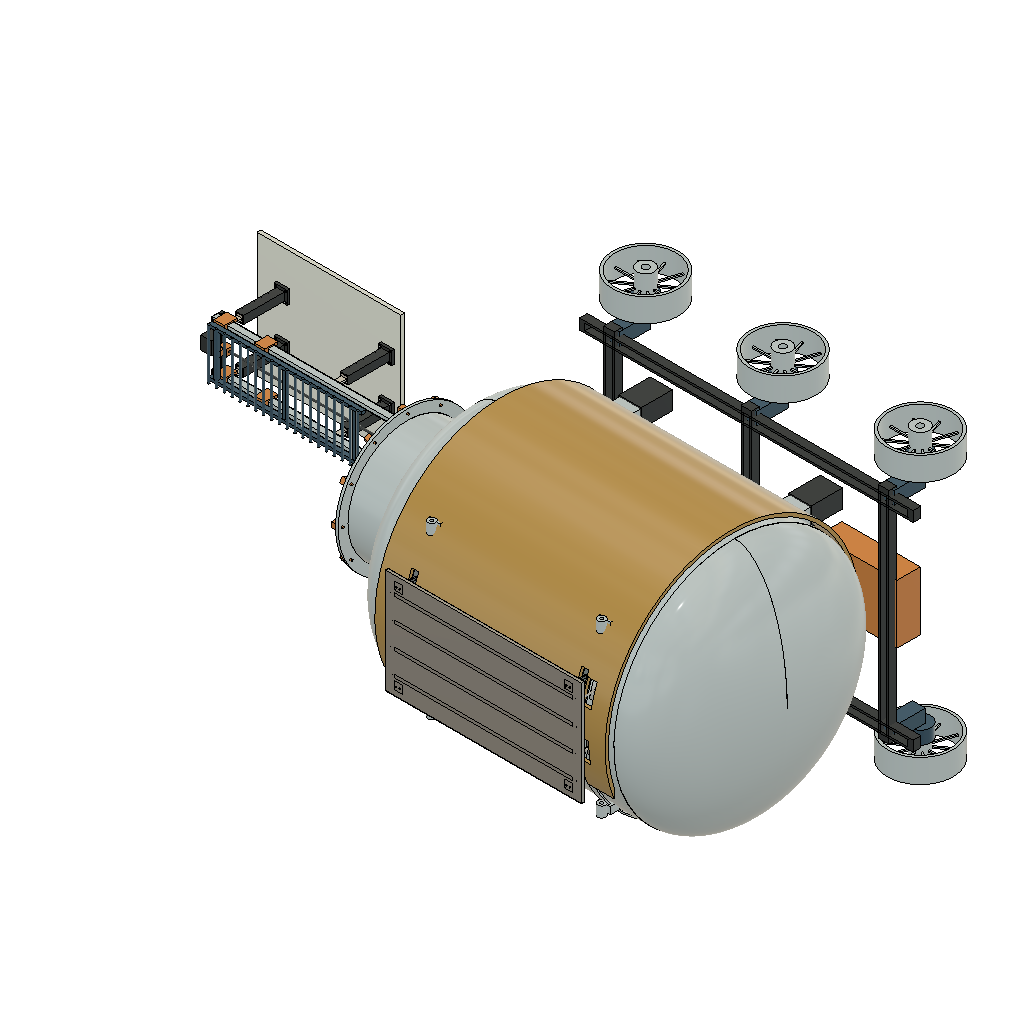
Moon_Movers_Concept (Autodesk Fusion 360 design; units mm, degrees)
part number: 2026-11-06-12-02-36-171
part number: 2026-11-06-12-02-36-298
part number: 2026-11-06-12-02-36-385
part number: 2026-11-06-12-02-36-736
part number: 2026-11-06-12-02-36-965
part number: 2026-11-06-12-02-37-148
part number: 2026-11-06-12-02-37-479
part number: 2026-11-06-12-02-37-621
part number: 2026-11-06-12-02-38-111
part number: 2026-11-06-12-02-38-668
part number: 2026-11-06-12-02-39-496
part number: 2026-11-06-12-02-40-582
part number: 2026-11-06-12-02-49-881
part number: 2026-11-06-12-02-51-442
part number: 2026-11-06-12-02-57-984
part number: 2026-11-06-12-02-58-352
part number: 2026-11-06-12-02-58-724
part number: 2026-11-06-12-02-59-677
part number: 2026-11-06-12-03-03-680
part number: 2026-11-06-12-03-06-963
part number: 2026-11-06-12-03-10-567
part number: 2026-11-06-12-03-15-193
part number: 2026-11-06-12-03-15-696
part number: 2026-11-06-12-26-54-918
part number: 2026-11-06-12-26-55-866
part number: 2026-11-06-12-26-57-242
part number: 2026-11-06-12-27-05-281
part number: 2026-11-06-13-09-31-180
part number: 2026-11-06-13-09-33-075
part number: 2026-11-06-13-09-46-178
part number: 2026-11-06-13-09-54-767
part number: 2026-11-06-13-09-58-459
part number: 2026-11-06-13-17-13-967
part number: 2026-11-06-13-17-21-409
part number: 2026-11-06-17-33-04-361
part number: 2026-11-06-17-33-16-586
part number: 2026-11-06-17-33-29-540
part number: 2026-11-06-17-34-03-018
Autodesk Fusion 360 part; units mm, degrees
(part 1 of 5)
sketch "Closed pressure shell meridian 3 mm" plane through (0, 0, 0) normal (0, 0, 1) x (1, 0, 0) in component "MM01 Pressure shell and neck"
  ellipse E0 centre (-900, 0) end of major axis (-900, 923) minor radius 403 (-900, 923) -> (-1303, 0) ccw
  ellipse E1 centre (-900, 0) end of major axis (-900, 920) minor radius 400 (-900, 920) -> (-1300, 0) ccw
  ellipse E2 centre (900, 0) end of major axis (900, 923) minor radius 403 (900, 923) -> (1303, 0) cw
  ellipse E3 centre (900, 0) end of major axis (900, 920) minor radius 400 (900, 920) -> (1300, 0) cw
  line L0 (-900, 923) -> (900, 923)
  line L1 (-900, 920) -> (900, 920)
  line L2 (-1303, 0) -> (-1300, 0)
  line L3 (1303, 0) -> (1300, 0)
revolve "Revolved barrel and ellipsoidal heads" add sketch "Closed pressure shell meridian 3 mm" angle 360 about axis through (1.75, 0, 0) along (1, 0, 0) contours  makes body 1 in component "MM01 Pressure shell and neck"
ref_plane "WorkPlane1" through (-1650, 0, 0) normal (1, 0, 0) x (0, 1, 0) in component "MM01 Pressure shell and neck"
sketch "Front pressure port sketch" plane through (-1650, 0, 0) normal (1, 0, 0) x (0, 0, -1) in component "MM01 Pressure shell and neck"
  circle A0 centre (0, 0) radius 450
extrude "Front pressure port" cut sketch "Front pressure port sketch" along normal blind 700 bodies 1 in component "MM01 Pressure shell and neck"
ref_plane "WorkPlane2" through (-1600, 0, 0) normal (1, 0, 0) x (0, 1, 0) in component "MM01 Pressure shell and neck"
sketch "Pressure transfer neck sketch" plane through (-1600, 0, 0) normal (1, 0, 0) x (0, 0, -1) in component "MM01 Pressure shell and neck"
  circle A0 centre (0, 0) radius 455
  circle A1 centre (0, 0) radius 450
extrude "Pressure transfer neck" add sketch "Pressure transfer neck sketch" along normal blind 400 bodies 1 in component "MM01 Pressure shell and neck"
ref_plane "WorkPlane1" through (-1620, 0, 0) normal (1, 0, 0) x (0, 1, 0) in component "MM02 Berthing flange and clear aperture"
sketch "Berthing face sketch" plane through (-1620, 0, 0) normal (1, 0, 0) x (0, 0, -1) in component "MM02 Berthing flange and clear aperture"
  circle A0 centre (0, 0) radius 530
extrude "Berthing face" add sketch "Berthing face sketch" along normal blind 20 separate body makes body 2 in component "MM02 Berthing flange and clear aperture"
ref_plane "WorkPlane2" through (0, 0, -235) normal (0, 0, 1) x (1, 0, 0) in component "MM02 Berthing flange and clear aperture"
sketch "Clear hatch 670 x 470 sketch" plane through (0, 0, -235) normal (0, 0, 1) x (1, 0, 0) in component "MM02 Berthing flange and clear aperture"
  line L0 (-1650, -335) -> (-1570, -335)
  line L1 (-1570, -335) -> (-1570, 335)
  line L2 (-1570, 335) -> (-1650, 335)
  line L3 (-1650, 335) -> (-1650, -335)
extrude "Clear hatch 670 x 470" cut sketch "Clear hatch 670 x 470 sketch" along normal blind 470 bodies 2 in component "MM02 Berthing flange and clear aperture"
ref_plane "WorkPlane3" through (-1640, 0, 0) normal (1, 0, 0) x (0, 1, 0) in component "MM02 Berthing flange and clear aperture"
sketch "Capture fastener bore 1 sketch" plane through (-1640, 0, 0) normal (1, 0, 0) x (0, 0, -1) in component "MM02 Berthing flange and clear aperture"
  circle A0 centre (0, 500) radius 8
extrude "Capture fastener bore 1" cut sketch "Capture fastener bore 1 sketch" along normal blind 60 bodies 2 in component "MM02 Berthing flange and clear aperture"
ref_plane "WorkPlane4" through (-1640, 0, 0) normal (1, 0, 0) x (0, 1, 0) in component "MM02 Berthing flange and clear aperture"
sketch "Capture fastener bore 2 sketch" plane through (-1640, 0, 0) normal (1, 0, 0) x (0, 0, -1) in component "MM02 Berthing flange and clear aperture"
  circle A0 centre (-250, 433.0127) radius 8
extrude "Capture fastener bore 2" cut sketch "Capture fastener bore 2 sketch" along normal blind 60 bodies 2 in component "MM02 Berthing flange and clear aperture"
ref_plane "WorkPlane5" through (-1640, 0, 0) normal (1, 0, 0) x (0, 1, 0) in component "MM02 Berthing flange and clear aperture"
sketch "Capture fastener bore 3 sketch" plane through (-1640, 0, 0) normal (1, 0, 0) x (0, 0, -1) in component "MM02 Berthing flange and clear aperture"
  circle A0 centre (-433.0127, 250) radius 8
extrude "Capture fastener bore 3" cut sketch "Capture fastener bore 3 sketch" along normal blind 60 bodies 2 in component "MM02 Berthing flange and clear aperture"
ref_plane "WorkPlane6" through (-1640, 0, 0) normal (1, 0, 0) x (0, 1, 0) in component "MM02 Berthing flange and clear aperture"
sketch "Capture fastener bore 4 sketch" plane through (-1640, 0, 0) normal (1, 0, 0) x (0, 0, -1) in component "MM02 Berthing flange and clear aperture"
  circle A0 centre (-500, 0) radius 8
extrude "Capture fastener bore 4" cut sketch "Capture fastener bore 4 sketch" along normal blind 60 bodies 2 in component "MM02 Berthing flange and clear aperture"
ref_plane "WorkPlane7" through (-1640, 0, 0) normal (1, 0, 0) x (0, 1, 0) in component "MM02 Berthing flange and clear aperture"
sketch "Capture fastener bore 5 sketch" plane through (-1640, 0, 0) normal (1, 0, 0) x (0, 0, -1) in component "MM02 Berthing flange and clear aperture"
  circle A0 centre (-433.0127, -250) radius 8
extrude "Capture fastener bore 5" cut sketch "Capture fastener bore 5 sketch" along normal blind 60 bodies 2 in component "MM02 Berthing flange and clear aperture"
ref_plane "WorkPlane8" through (-1640, 0, 0) normal (1, 0, 0) x (0, 1, 0) in component "MM02 Berthing flange and clear aperture"
sketch "Capture fastener bore 6 sketch" plane through (-1640, 0, 0) normal (1, 0, 0) x (0, 0, -1) in component "MM02 Berthing flange and clear aperture"
  circle A0 centre (-250, -433.0127) radius 8
extrude "Capture fastener bore 6" cut sketch "Capture fastener bore 6 sketch" along normal blind 60 bodies 2 in component "MM02 Berthing flange and clear aperture"
ref_plane "WorkPlane9" through (-1640, 0, 0) normal (1, 0, 0) x (0, 1, 0) in component "MM02 Berthing flange and clear aperture"
sketch "Capture fastener bore 7 sketch" plane through (-1640, 0, 0) normal (1, 0, 0) x (0, 0, -1) in component "MM02 Berthing flange and clear aperture"
  circle A0 centre (0, -500) radius 8
extrude "Capture fastener bore 7" cut sketch "Capture fastener bore 7 sketch" along normal blind 60 bodies 2 in component "MM02 Berthing flange and clear aperture"
ref_plane "WorkPlane10" through (-1640, 0, 0) normal (1, 0, 0) x (0, 1, 0) in component "MM02 Berthing flange and clear aperture"
sketch "Capture fastener bore 8 sketch" plane through (-1640, 0, 0) normal (1, 0, 0) x (0, 0, -1) in component "MM02 Berthing flange and clear aperture"
  circle A0 centre (250, -433.0127) radius 8
extrude "Capture fastener bore 8" cut sketch "Capture fastener bore 8 sketch" along normal blind 60 bodies 2 in component "MM02 Berthing flange and clear aperture"
ref_plane "WorkPlane11" through (-1640, 0, 0) normal (1, 0, 0) x (0, 1, 0) in component "MM02 Berthing flange and clear aperture"
sketch "Capture fastener bore 9 sketch" plane through (-1640, 0, 0) normal (1, 0, 0) x (0, 0, -1) in component "MM02 Berthing flange and clear aperture"
  circle A0 centre (433.0127, -250) radius 8
extrude "Capture fastener bore 9" cut sketch "Capture fastener bore 9 sketch" along normal blind 60 bodies 2 in component "MM02 Berthing flange and clear aperture"
ref_plane "WorkPlane12" through (-1640, 0, 0) normal (1, 0, 0) x (0, 1, 0) in component "MM02 Berthing flange and clear aperture"
sketch "Capture fastener bore 10 sketch" plane through (-1640, 0, 0) normal (1, 0, 0) x (0, 0, -1) in component "MM02 Berthing flange and clear aperture"
  circle A0 centre (500, 0) radius 8
extrude "Capture fastener bore 10" cut sketch "Capture fastener bore 10 sketch" along normal blind 60 bodies 2 in component "MM02 Berthing flange and clear aperture"
ref_plane "WorkPlane13" through (-1640, 0, 0) normal (1, 0, 0) x (0, 1, 0) in component "MM02 Berthing flange and clear aperture"
sketch "Capture fastener bore 11 sketch" plane through (-1640, 0, 0) normal (1, 0, 0) x (0, 0, -1) in component "MM02 Berthing flange and clear aperture"
  circle A0 centre (433.0127, 250) radius 8
extrude "Capture fastener bore 11" cut sketch "Capture fastener bore 11 sketch" along normal blind 60 bodies 2 in component "MM02 Berthing flange and clear aperture"
ref_plane "WorkPlane14" through (-1640, 0, 0) normal (1, 0, 0) x (0, 1, 0) in component "MM02 Berthing flange and clear aperture"
sketch "Capture fastener bore 12 sketch" plane through (-1640, 0, 0) normal (1, 0, 0) x (0, 0, -1) in component "MM02 Berthing flange and clear aperture"
  circle A0 centre (250, 433.0127) radius 8
extrude "Capture fastener bore 12" cut sketch "Capture fastener bore 12 sketch" along normal blind 60 bodies 2 in component "MM02 Berthing flange and clear aperture"
ref_plane "WorkPlane1" through (0, 0, -260) normal (0, 0, 1) x (1, 0, 0) in component "MM03 Inward opening pressure hatch"
sketch "Pressure door leaf sketch" plane through (0, 0, -260) normal (0, 0, 1) x (1, 0, 0) in component "MM03 Inward opening pressure hatch"
  line L0 (-1600, -360) -> (-1580, -360)
  line L1 (-1580, -360) -> (-1580, 360)
  line L2 (-1580, 360) -> (-1600, 360)
  line L3 (-1600, 360) -> (-1600, -360)
extrude "Pressure door leaf" add sketch "Pressure door leaf sketch" along normal blind 520 separate body makes body 3 in component "MM03 Inward opening pressure hatch"
ref_plane "WorkPlane2" through (0, 0, -200) normal (0, 0, 1) x (1, 0, 0) in component "MM03 Inward opening pressure hatch"
sketch "Door stiffener sketch" plane through (0, 0, -200) normal (0, 0, 1) x (1, 0, 0) in component "MM03 Inward opening pressure hatch"
  line L0 (-1580, -252.5) -> (-1550, -252.5)
  line L1 (-1550, -252.5) -> (-1550, -227.5)
  line L2 (-1550, -227.5) -> (-1580, -227.5)
  line L3 (-1580, -227.5) -> (-1580, -252.5)
extrude "Door stiffener" add sketch "Door stiffener sketch" along normal blind 400 separate body makes body 4 in component "MM03 Inward opening pressure hatch"
ref_plane "WorkPlane3" through (0, 0, -200) normal (0, 0, 1) x (1, 0, 0) in component "MM03 Inward opening pressure hatch"
sketch "Door stiffener sketch (1)" plane through (0, 0, -200) normal (0, 0, 1) x (1, 0, 0) in component "MM03 Inward opening pressure hatch"
  line L0 (-1580, 227.5) -> (-1550, 227.5)
  line L1 (-1550, 227.5) -> (-1550, 252.5)
  line L2 (-1550, 252.5) -> (-1580, 252.5)
  line L3 (-1580, 252.5) -> (-1580, 227.5)
extrude "Door stiffener (1)" add sketch "Door stiffener sketch (1)" along normal blind 400 separate body makes body 5 in component "MM03 Inward opening pressure hatch"
ref_plane "WorkPlane4" through (0, 0, -220) normal (0, 0, 1) x (1, 0, 0) in component "MM03 Inward opening pressure hatch"
sketch "Vertical hinge shaft sketch" plane through (0, 0, -220) normal (0, 0, 1) x (1, 0, 0) in component "MM03 Inward opening pressure hatch"
  circle A0 centre (-1565, -375) radius 10
extrude "Vertical hinge shaft" add sketch "Vertical hinge shaft sketch" along normal blind 440 separate body makes body 6 in component "MM03 Inward opening pressure hatch"
ref_plane "WorkPlane5" through (0, 0, -210) normal (0, 0, 1) x (1, 0, 0) in component "MM03 Inward opening pressure hatch"
sketch "Hinge arm sketch" plane through (0, 0, -210) normal (0, 0, 1) x (1, 0, 0) in component "MM03 Inward opening pressure hatch"
  line L0 (-1590, -375) -> (-1550, -375)
  line L1 (-1550, -375) -> (-1550, -325)
  line L2 (-1550, -325) -> (-1590, -325)
  line L3 (-1590, -325) -> (-1590, -375)
extrude "Hinge arm" add sketch "Hinge arm sketch" along normal blind 30 separate body makes body 7 in component "MM03 Inward opening pressure hatch"
ref_plane "WorkPlane6" through (0, 0, 180) normal (0, 0, 1) x (1, 0, 0) in component "MM03 Inward opening pressure hatch"
sketch "Hinge arm sketch (1)" plane through (0, 0, 180) normal (0, 0, 1) x (1, 0, 0) in component "MM03 Inward opening pressure hatch"
  line L0 (-1590, -375) -> (-1550, -375)
  line L1 (-1550, -375) -> (-1550, -325)
  line L2 (-1550, -325) -> (-1590, -325)
  line L3 (-1590, -325) -> (-1590, -375)
extrude "Hinge arm (1)" add sketch "Hinge arm sketch (1)" along normal blind 30 separate body makes body 8 in component "MM03 Inward opening pressure hatch"
ref_plane "WorkPlane1" through (0, 0, -255) normal (0, 0, 1) x (1, 0, 0) in component "MM04 Twin hatch seal lands"
sketch "Hatch seal envelope sketch" plane through (0, 0, -255) normal (0, 0, 1) x (1, 0, 0) in component "MM04 Twin hatch seal lands"
  line L0 (-1601.4, -355) -> (-1600, -355)
  line L1 (-1600, -355) -> (-1600, 355)
  line L2 (-1600, 355) -> (-1601.4, 355)
  line L3 (-1601.4, 355) -> (-1601.4, -355)
extrude "Hatch seal envelope" add sketch "Hatch seal envelope sketch" along normal blind 510 separate body makes body 9 in component "MM04 Twin hatch seal lands"
ref_plane "WorkPlane2" through (0, 0, -250) normal (0, 0, 1) x (1, 0, 0) in component "MM04 Twin hatch seal lands"
sketch "Seal opening sketch" plane through (0, 0, -250) normal (0, 0, 1) x (1, 0, 0) in component "MM04 Twin hatch seal lands"
  line L0 (-1603.2, -350) -> (-1598.2, -350)
  line L1 (-1598.2, -350) -> (-1598.2, 350)
  line L2 (-1598.2, 350) -> (-1603.2, 350)
  line L3 (-1603.2, 350) -> (-1603.2, -350)
extrude "Seal opening" cut sketch "Seal opening sketch" along normal blind 500 bodies 9 in component "MM04 Twin hatch seal lands"
ref_plane "WorkPlane3" through (0, 0, -245) normal (0, 0, 1) x (1, 0, 0) in component "MM04 Twin hatch seal lands"
sketch "Hatch seal envelope sketch (1)" plane through (0, 0, -245) normal (0, 0, 1) x (1, 0, 0) in component "MM04 Twin hatch seal lands"
  line L0 (-1601.4, -345) -> (-1600, -345)
  line L1 (-1600, -345) -> (-1600, 345)
  line L2 (-1600, 345) -> (-1601.4, 345)
  line L3 (-1601.4, 345) -> (-1601.4, -345)
extrude "Hatch seal envelope (1)" add sketch "Hatch seal envelope sketch (1)" along normal blind 490 separate body makes body 10 in component "MM04 Twin hatch seal lands"
ref_plane "WorkPlane4" through (0, 0, -240) normal (0, 0, 1) x (1, 0, 0) in component "MM04 Twin hatch seal lands"
sketch "Seal opening sketch (1)" plane through (0, 0, -240) normal (0, 0, 1) x (1, 0, 0) in component "MM04 Twin hatch seal lands"
  line L0 (-1603.2, -340) -> (-1598.2, -340)
  line L1 (-1598.2, -340) -> (-1598.2, 340)
  line L2 (-1598.2, 340) -> (-1603.2, 340)
  line L3 (-1603.2, 340) -> (-1603.2, -340)
extrude "Seal opening (1)" cut sketch "Seal opening sketch (1)" along normal blind 480 bodies 9 10 in component "MM04 Twin hatch seal lands"
ref_plane "WorkPlane1" through (0, 0, -20) normal (0, 0, 1) x (1, 0, 0) in component "MM05 Hard capture latch station"
sketch "Clamp reaction block sketch" plane through (0, 0, -20) normal (0, 0, 1) x (1, 0, 0) in component "MM05 Hard capture latch station"
  line L0 (-1654.5, 475) -> (-1619.5, 475)
  line L1 (-1619.5, 475) -> (-1619.5, 525)
  line L2 (-1619.5, 525) -> (-1654.5, 525)
  line L3 (-1654.5, 525) -> (-1654.5, 475)
extrude "Clamp reaction block" add sketch "Clamp reaction block sketch" along normal blind 40 separate body makes body 11 in component "MM05 Hard capture latch station"
ref_plane "WorkPlane2" through (-1665, 0, 0) normal (1, 0, 0) x (0, 1, 0) in component "MM05 Hard capture latch station"
sketch "M14 equivalent tension shank sketch" plane through (-1665, 0, 0) normal (1, 0, 0) x (0, 0, -1) in component "MM05 Hard capture latch station"
  circle A0 centre (0, 500) radius 7
extrude "M14 equivalent tension shank" add sketch "M14 equivalent tension shank sketch" along normal blind 75 separate body makes body 12 in component "MM05 Hard capture latch station"
ref_plane "WorkPlane1" through (-880, 0, 0) normal (1, 0, 0) x (0, 1, 0) in component "MM07 MLI blanket envelope"
sketch "MLI blanket envelope sketch" plane through (-880, 0, 0) normal (1, 0, 0) x (0, 0, -1) in component "MM07 MLI blanket envelope"
  circle A0 centre (0, 0) radius 970
  circle A1 centre (0, 0) radius 945
extrude "MLI blanket envelope" add sketch "MLI blanket envelope sketch" along normal blind 1760 separate body makes body 13 in component "MM07 MLI blanket envelope"
ref_plane "WorkPlane2" through (0, 0, 0) normal (0, 0, 1) x (1, 0, 0) in component "MM07 MLI blanket envelope"
sketch "Engineering inspection cutaway sketch" plane through (0, 0, 0) normal (0, 0, 1) x (1, 0, 0) in component "MM07 MLI blanket envelope"
  line L0 (-950, -1300) -> (950, -1300)
  line L1 (950, -1300) -> (950, 0)
  line L2 (950, 0) -> (-950, 0)
  line L3 (-950, 0) -> (-950, -1300)
extrude "Engineering inspection cutaway" cut sketch "Engineering inspection cutaway sketch" along normal blind 900 bodies 13 in component "MM07 MLI blanket envelope"
ref_plane "WorkPlane1" through (-680, 0, 0) normal (1, 0, 0) x (0, 1, 0) in component "MM08 Load spreading band -650"
sketch "Circumferential band sketch" plane through (-680, 0, 0) normal (1, 0, 0) x (0, 0, -1) in component "MM08 Load spreading band -650"
  circle A0 centre (0, 0) radius 940
  circle A1 centre (0, 0) radius 930
extrude "Circumferential band" add sketch "Circumferential band sketch" along normal blind 60 separate body makes body 14 in component "MM08 Load spreading band -650"
ref_plane "WorkPlane2" through (0, 0, -780) normal (0, 0, 1) x (1, 0, 0) in component "MM08 Load spreading band -650"
sketch "Cradle pad sketch" plane through (0, 0, -780) normal (0, 0, 1) x (1, 0, 0) in component "MM08 Load spreading band -650"
  line L0 (-730, -670) -> (-570, -670)
  line L1 (-570, -670) -> (-570, -550)
  line L2 (-570, -550) -> (-730, -550)
  line L3 (-730, -550) -> (-730, -670)
extrude "Cradle pad" add sketch "Cradle pad sketch" along normal blind 120 separate body makes body 15 in component "MM08 Load spreading band -650"
ref_plane "WorkPlane3" through (0, 0, 675) normal (0, 0, 1) x (1, 0, 0) in component "MM08 Load spreading band -650"
sketch "Handling lug base sketch" plane through (0, 0, 675) normal (0, 0, 1) x (1, 0, 0) in component "MM08 Load spreading band -650"
  line L0 (-695, -637.5) -> (-605, -637.5)
  line L1 (-605, -637.5) -> (-605, -582.5)
  line L2 (-605, -582.5) -> (-695, -582.5)
  line L3 (-695, -582.5) -> (-695, -637.5)
extrude "Handling lug base" add sketch "Handling lug base sketch" along normal blind 70 separate body makes body 16 in component "MM08 Load spreading band -650"
ref_plane "WorkPlane4" through (0, -650, 0) normal (0, 1, 0) x (0, 0, 1) in component "MM08 Load spreading band -650"
sketch "Lift trunnion sketch" plane through (0, -650, 0) normal (0, 1, 0) x (1, 0, 0) in component "MM08 Load spreading band -650"
  circle A0 centre (-650, -765) radius 30
  circle A1 centre (-650, -765) radius 12
extrude "Lift trunnion" add sketch "Lift trunnion sketch" along normal blind 80 separate body makes body 17 in component "MM08 Load spreading band -650"
ref_plane "WorkPlane5" through (0, 0, -780) normal (0, 0, 1) x (1, 0, 0) in component "MM08 Load spreading band -650"
sketch "Cradle pad sketch (1)" plane through (0, 0, -780) normal (0, 0, 1) x (1, 0, 0) in component "MM08 Load spreading band -650"
  line L0 (-730, 550) -> (-570, 550)
  line L1 (-570, 550) -> (-570, 670)
  line L2 (-570, 670) -> (-730, 670)
  line L3 (-730, 670) -> (-730, 550)
extrude "Cradle pad (1)" add sketch "Cradle pad sketch (1)" along normal blind 120 separate body makes body 18 in component "MM08 Load spreading band -650"
ref_plane "WorkPlane6" through (0, 0, 675) normal (0, 0, 1) x (1, 0, 0) in component "MM08 Load spreading band -650"
sketch "Handling lug base sketch (1)" plane through (0, 0, 675) normal (0, 0, 1) x (1, 0, 0) in component "MM08 Load spreading band -650"
  line L0 (-695, 582.5) -> (-605, 582.5)
  line L1 (-605, 582.5) -> (-605, 637.5)
  line L2 (-605, 637.5) -> (-695, 637.5)
  line L3 (-695, 637.5) -> (-695, 582.5)
extrude "Handling lug base (1)" add sketch "Handling lug base sketch (1)" along normal blind 70 separate body makes body 19 in component "MM08 Load spreading band -650"
ref_plane "WorkPlane7" through (0, 570, 0) normal (0, 1, 0) x (0, 0, 1) in component "MM08 Load spreading band -650"
sketch "Lift trunnion sketch (1)" plane through (0, 570, 0) normal (0, 1, 0) x (1, 0, 0) in component "MM08 Load spreading band -650"
  circle A0 centre (-650, -765) radius 30
  circle A1 centre (-650, -765) radius 12
extrude "Lift trunnion (1)" add sketch "Lift trunnion sketch (1)" along normal blind 80 separate body makes body 20 in component "MM08 Load spreading band -650"
ref_plane "WorkPlane1" through (620, 0, 0) normal (1, 0, 0) x (0, 1, 0) in component "MM08 Load spreading band 650"
sketch "Circumferential band sketch (2)" plane through (620, 0, 0) normal (1, 0, 0) x (0, 0, -1) in component "MM08 Load spreading band 650"
  circle A0 centre (0, 0) radius 940
  circle A1 centre (0, 0) radius 930
extrude "Circumferential band'" add sketch "Circumferential band sketch (2)" along normal blind 60 separate body makes body 21 in component "MM08 Load spreading band 650"
ref_plane "WorkPlane2" through (0, 0, -780) normal (0, 0, 1) x (1, 0, 0) in component "MM08 Load spreading band 650"
sketch "Cradle pad sketch (2)" plane through (0, 0, -780) normal (0, 0, 1) x (1, 0, 0) in component "MM08 Load spreading band 650"
  line L0 (570, -670) -> (730, -670)
  line L1 (730, -670) -> (730, -550)
  line L2 (730, -550) -> (570, -550)
  line L3 (570, -550) -> (570, -670)
extrude "Cradle pad'" add sketch "Cradle pad sketch (2)" along normal blind 120 separate body makes body 22 in component "MM08 Load spreading band 650"
ref_plane "WorkPlane3" through (0, 0, 675) normal (0, 0, 1) x (1, 0, 0) in component "MM08 Load spreading band 650"
sketch "Handling lug base sketch (2)" plane through (0, 0, 675) normal (0, 0, 1) x (1, 0, 0) in component "MM08 Load spreading band 650"
  line L0 (605, -637.5) -> (695, -637.5)
  line L1 (695, -637.5) -> (695, -582.5)
  line L2 (695, -582.5) -> (605, -582.5)
  line L3 (605, -582.5) -> (605, -637.5)
extrude "Handling lug base'" add sketch "Handling lug base sketch (2)" along normal blind 70 separate body makes body 23 in component "MM08 Load spreading band 650"
ref_plane "WorkPlane4" through (0, -650, 0) normal (0, 1, 0) x (0, 0, 1) in component "MM08 Load spreading band 650"
sketch "Lift trunnion sketch (2)" plane through (0, -650, 0) normal (0, 1, 0) x (1, 0, 0) in component "MM08 Load spreading band 650"
  circle A0 centre (650, -765) radius 30
  circle A1 centre (650, -765) radius 12
extrude "Lift trunnion'" add sketch "Lift trunnion sketch (2)" along normal blind 80 separate body makes body 24 in component "MM08 Load spreading band 650"
ref_plane "WorkPlane5" through (0, 0, -780) normal (0, 0, 1) x (1, 0, 0) in component "MM08 Load spreading band 650"
sketch "Cradle pad sketch (1) (2)" plane through (0, 0, -780) normal (0, 0, 1) x (1, 0, 0) in component "MM08 Load spreading band 650"
  line L0 (570, 550) -> (730, 550)
  line L1 (730, 550) -> (730, 670)
  line L2 (730, 670) -> (570, 670)
  line L3 (570, 670) -> (570, 550)
extrude "Cradle pad (1)'" add sketch "Cradle pad sketch (1) (2)" along normal blind 120 separate body makes body 25 in component "MM08 Load spreading band 650"
ref_plane "WorkPlane6" through (0, 0, 675) normal (0, 0, 1) x (1, 0, 0) in component "MM08 Load spreading band 650"
sketch "Handling lug base sketch (1) (2)" plane through (0, 0, 675) normal (0, 0, 1) x (1, 0, 0) in component "MM08 Load spreading band 650"
  line L0 (605, 582.5) -> (695, 582.5)
  line L1 (695, 582.5) -> (695, 637.5)
  line L2 (695, 637.5) -> (605, 637.5)
  line L3 (605, 637.5) -> (605, 582.5)
extrude "Handling lug base (1)'" add sketch "Handling lug base sketch (1) (2)" along normal blind 70 separate body makes body 26 in component "MM08 Load spreading band 650"
ref_plane "WorkPlane7" through (0, 570, 0) normal (0, 1, 0) x (0, 0, 1) in component "MM08 Load spreading band 650"
sketch "Lift trunnion sketch (1) (2)" plane through (0, 570, 0) normal (0, 1, 0) x (1, 0, 0) in component "MM08 Load spreading band 650"
  circle A0 centre (650, -765) radius 30
  circle A1 centre (650, -765) radius 12
extrude "Lift trunnion (1)'" add sketch "Lift trunnion sketch (1) (2)" along normal blind 80 separate body makes body 27 in component "MM08 Load spreading band 650"
ref_plane "WorkPlane1" through (0, 0, -124) normal (0, 0, 1) x (1, 0, 0) in component "MM09 Cargo transfer bag"
sketch "CTB maximum envelope sketch" plane through (0, 0, -124) normal (0, 0, 1) x (1, 0, 0) in component "MM09 Cargo transfer bag"
  line L0 (-251, -212.5) -> (251, -212.5)
  line L1 (251, -212.5) -> (251, 212.5)
  line L2 (251, 212.5) -> (-251, 212.5)
  line L3 (-251, 212.5) -> (-251, -212.5)
extrude "CTB maximum envelope" add sketch "CTB maximum envelope sketch" along normal blind 248 separate body makes body 28 in component "MM09 Cargo transfer bag"
fillet "Soft bag corner envelope" radius 8 12 edges at (0, 212.5, -124) (-251, 212.5, 0) (0, 212.5, 124) (251, 212.5, 0) (251, 0, -124) (251, 0, 124) (251, -212.5, 0) (0, -212.5, -124) (0, -212.5, 124) (-251, -212.5, 0) (-251, 0, -124) (-251, 0, 124) on bodies 28 in component "MM09 Cargo transfer bag"
ref_plane "WorkPlane2" through (0, 0, 123) normal (0, 0, 1) x (1, 0, 0) in component "MM09 Cargo transfer bag"
sketch "Restraint strap envelope sketch" plane through (0, 0, 123) normal (0, 0, 1) x (1, 0, 0) in component "MM09 Cargo transfer bag"
  line L0 (-240, -155) -> (240, -155)
  line L1 (240, -155) -> (240, -135)
  line L2 (240, -135) -> (-240, -135)
  line L3 (-240, -135) -> (-240, -155)
extrude "Restraint strap envelope" add sketch "Restraint strap envelope sketch" along normal blind 1 separate body makes body 29 in component "MM09 Cargo transfer bag"
ref_plane "WorkPlane3" through (0, 0, 123) normal (0, 0, 1) x (1, 0, 0) in component "MM09 Cargo transfer bag"
sketch "Restraint strap envelope sketch (1)" plane through (0, 0, 123) normal (0, 0, 1) x (1, 0, 0) in component "MM09 Cargo transfer bag"
  line L0 (-240, 135) -> (240, 135)
  line L1 (240, 135) -> (240, 155)
  line L2 (240, 155) -> (-240, 155)
  line L3 (-240, 155) -> (-240, 135)
extrude "Restraint strap envelope (1)" add sketch "Restraint strap envelope sketch (1)" along normal blind 1 separate body makes body 30 in component "MM09 Cargo transfer bag"
ref_plane "WorkPlane1" through (0, 0, -128) normal (0, 0, 1) x (1, 0, 0) in component "MM10 Reconfigurable CTB tray"
sketch "Light tray perimeter sketch" plane through (0, 0, -128) normal (0, 0, 1) x (1, 0, 0) in component "MM10 Reconfigurable CTB tray"
  line L0 (-251, -212.5) -> (251, -212.5)
  line L1 (251, -212.5) -> (251, 212.5)
  line L2 (251, 212.5) -> (-251, 212.5)
  line L3 (-251, 212.5) -> (-251, -212.5)
  line L4 (-231, -192.5) -> (231, -192.5)
  line L5 (231, -192.5) -> (231, 192.5)
  line L6 (231, 192.5) -> (-231, 192.5)
  line L7 (-231, 192.5) -> (-231, -192.5)
extrude "Light tray perimeter" add sketch "Light tray perimeter sketch" along normal blind 2 separate body makes body 31 in component "MM10 Reconfigurable CTB tray"
ref_plane "WorkPlane2" through (0, 0, -128) normal (0, 0, 1) x (1, 0, 0) in component "MM10 Reconfigurable CTB tray"
sketch "Conveyor traction strip sketch" plane through (0, 0, -128) normal (0, 0, 1) x (1, 0, 0) in component "MM10 Reconfigurable CTB tray"
  line L0 (-251, -15) -> (251, -15)
  line L1 (251, -15) -> (251, 15)
  line L2 (251, 15) -> (-251, 15)
  line L3 (-251, 15) -> (-251, -15)
extrude "Conveyor traction strip" add sketch "Conveyor traction strip sketch" along normal blind 2 separate body makes body 32 in component "MM10 Reconfigurable CTB tray"
ref_plane "WorkPlane3" through (0, 0, -126.75) normal (0, 0, 1) x (1, 0, 0) in component "MM10 Reconfigurable CTB tray"
sketch "Tray cross strap sketch" plane through (0, 0, -126.75) normal (0, 0, 1) x (1, 0, 0) in component "MM10 Reconfigurable CTB tray"
  line L0 (-135, -212.5) -> (-115, -212.5)
  line L1 (-115, -212.5) -> (-115, 212.5)
  line L2 (-115, 212.5) -> (-135, 212.5)
  line L3 (-135, 212.5) -> (-135, -212.5)
extrude "Tray cross strap" add sketch "Tray cross strap sketch" along normal blind 2.75 separate body makes body 33 in component "MM10 Reconfigurable CTB tray"
ref_plane "WorkPlane4" through (0, 0, -126.75) normal (0, 0, 1) x (1, 0, 0) in component "MM10 Reconfigurable CTB tray"
sketch "Tray cross strap sketch (1)" plane through (0, 0, -126.75) normal (0, 0, 1) x (1, 0, 0) in component "MM10 Reconfigurable CTB tray"
  line L0 (115, -212.5) -> (135, -212.5)
  line L1 (135, -212.5) -> (135, 212.5)
  line L2 (135, 212.5) -> (115, 212.5)
  line L3 (115, 212.5) -> (115, -212.5)
extrude "Tray cross strap (1)" add sketch "Tray cross strap sketch (1)" along normal blind 2.75 separate body makes body 34 in component "MM10 Reconfigurable CTB tray"
ref_plane "WorkPlane1" through (0, 0, -696) normal (0, 0, 1) x (1, 0, 0) in component "MM11 Rack rails and restraint stops"
sketch "Channel support rail sketch" plane through (0, 0, -696) normal (0, 0, 1) x (1, 0, 0) in component "MM11 Rack rails and restraint stops"
  line L0 (-240, -412.5) -> (820, -412.5)
  line L1 (820, -412.5) -> (820, -402.5)
  line L2 (820, -402.5) -> (-240, -402.5)
  line L3 (-240, -402.5) -> (-240, -412.5)
extrude "Channel support rail" add sketch "Channel support rail sketch" along normal blind 8 separate body makes body 35 in component "MM11 Rack rails and restraint stops"
ref_plane "WorkPlane2" through (0, 0, -696) normal (0, 0, 1) x (1, 0, 0) in component "MM11 Rack rails and restraint stops"
sketch "Channel support rail sketch (1)" plane through (0, 0, -696) normal (0, 0, 1) x (1, 0, 0) in component "MM11 Rack rails and restraint stops"
  line L0 (-240, -32.5) -> (820, -32.5)
  line L1 (820, -32.5) -> (820, -22.5)
  line L2 (820, -22.5) -> (-240, -22.5)
  line L3 (-240, -22.5) -> (-240, -32.5)
extrude "Channel support rail (1)" add sketch "Channel support rail sketch (1)" along normal blind 8 separate body makes body 36 in component "MM11 Rack rails and restraint stops"
ref_plane "WorkPlane3" through (0, 0, -696) normal (0, 0, 1) x (1, 0, 0) in component "MM11 Rack rails and restraint stops"
sketch "Channel support rail sketch (2)" plane through (0, 0, -696) normal (0, 0, 1) x (1, 0, 0) in component "MM11 Rack rails and restraint stops"
  line L0 (-240, 22.5) -> (820, 22.5)
  line L1 (820, 22.5) -> (820, 32.5)
  line L2 (820, 32.5) -> (-240, 32.5)
  line L3 (-240, 32.5) -> (-240, 22.5)
extrude "Channel support rail (2)" add sketch "Channel support rail sketch (2)" along normal blind 8 separate body makes body 37 in component "MM11 Rack rails and restraint stops"
ref_plane "WorkPlane4" through (0, 0, -696) normal (0, 0, 1) x (1, 0, 0) in component "MM11 Rack rails and restraint stops"
sketch "Channel support rail sketch (3)" plane through (0, 0, -696) normal (0, 0, 1) x (1, 0, 0) in component "MM11 Rack rails and restraint stops"
  line L0 (-240, 402.5) -> (820, 402.5)
  line L1 (820, 402.5) -> (820, 412.5)
  line L2 (820, 412.5) -> (-240, 412.5)
  line L3 (-240, 412.5) -> (-240, 402.5)
extrude "Channel support rail (3)" add sketch "Channel support rail sketch (3)" along normal blind 8 separate body makes body 38 in component "MM11 Rack rails and restraint stops"
ref_plane "WorkPlane5" through (0, 0, -416) normal (0, 0, 1) x (1, 0, 0) in component "MM11 Rack rails and restraint stops"
sketch "Channel support rail sketch (4)" plane through (0, 0, -416) normal (0, 0, 1) x (1, 0, 0) in component "MM11 Rack rails and restraint stops"
  line L0 (-240, -630) -> (820, -630)
  line L1 (820, -630) -> (820, -620)
  line L2 (820, -620) -> (-240, -620)
  line L3 (-240, -620) -> (-240, -630)
extrude "Channel support rail (4)" add sketch "Channel support rail sketch (4)" along normal blind 8 separate body makes body 39 in component "MM11 Rack rails and restraint stops"
ref_plane "WorkPlane6" through (0, 0, -416) normal (0, 0, 1) x (1, 0, 0) in component "MM11 Rack rails and restraint stops"
sketch "Channel support rail sketch (5)" plane through (0, 0, -416) normal (0, 0, 1) x (1, 0, 0) in component "MM11 Rack rails and restraint stops"
  line L0 (-240, -250) -> (820, -250)
  line L1 (820, -250) -> (820, -240)
  line L2 (820, -240) -> (-240, -240)
  line L3 (-240, -240) -> (-240, -250)
extrude "Channel support rail (5)" add sketch "Channel support rail sketch (5)" along normal blind 8 separate body makes body 40 in component "MM11 Rack rails and restraint stops"
ref_plane "WorkPlane7" through (0, 0, -416) normal (0, 0, 1) x (1, 0, 0) in component "MM11 Rack rails and restraint stops"
sketch "Channel support rail sketch (6)" plane through (0, 0, -416) normal (0, 0, 1) x (1, 0, 0) in component "MM11 Rack rails and restraint stops"
  line L0 (-240, -195) -> (820, -195)
  line L1 (820, -195) -> (820, -185)
  line L2 (820, -185) -> (-240, -185)
  line L3 (-240, -185) -> (-240, -195)
extrude "Channel support rail (6)" add sketch "Channel support rail sketch (6)" along normal blind 8 separate body makes body 41 in component "MM11 Rack rails and restraint stops"
ref_plane "WorkPlane8" through (0, 0, -416) normal (0, 0, 1) x (1, 0, 0) in component "MM11 Rack rails and restraint stops"
sketch "Channel support rail sketch (7)" plane through (0, 0, -416) normal (0, 0, 1) x (1, 0, 0) in component "MM11 Rack rails and restraint stops"
  line L0 (-240, 185) -> (820, 185)
  line L1 (820, 185) -> (820, 195)
  line L2 (820, 195) -> (-240, 195)
  line L3 (-240, 195) -> (-240, 185)
extrude "Channel support rail (7)" add sketch "Channel support rail sketch (7)" along normal blind 8 separate body makes body 42 in component "MM11 Rack rails and restraint stops"
ref_plane "WorkPlane9" through (0, 0, -416) normal (0, 0, 1) x (1, 0, 0) in component "MM11 Rack rails and restraint stops"
sketch "Channel support rail sketch (8)" plane through (0, 0, -416) normal (0, 0, 1) x (1, 0, 0) in component "MM11 Rack rails and restraint stops"
  line L0 (-240, 240) -> (820, 240)
  line L1 (820, 240) -> (820, 250)
  line L2 (820, 250) -> (-240, 250)
  line L3 (-240, 250) -> (-240, 240)
extrude "Channel support rail (8)" add sketch "Channel support rail sketch (8)" along normal blind 8 separate body makes body 43 in component "MM11 Rack rails and restraint stops"
ref_plane "WorkPlane10" through (0, 0, -416) normal (0, 0, 1) x (1, 0, 0) in component "MM11 Rack rails and restraint stops"
sketch "Channel support rail sketch (9)" plane through (0, 0, -416) normal (0, 0, 1) x (1, 0, 0) in component "MM11 Rack rails and restraint stops"
  line L0 (-240, 620) -> (820, 620)
  line L1 (820, 620) -> (820, 630)
  line L2 (820, 630) -> (-240, 630)
  line L3 (-240, 630) -> (-240, 620)
extrude "Channel support rail (9)" add sketch "Channel support rail sketch (9)" along normal blind 8 separate body makes body 44 in component "MM11 Rack rails and restraint stops"
ref_plane "WorkPlane11" through (0, 0, -136) normal (0, 0, 1) x (1, 0, 0) in component "MM11 Rack rails and restraint stops"
sketch "Channel support rail sketch (10)" plane through (0, 0, -136) normal (0, 0, 1) x (1, 0, 0) in component "MM11 Rack rails and restraint stops"
  line L0 (-240, -630) -> (820, -630)
  line L1 (820, -630) -> (820, -620)
  line L2 (820, -620) -> (-240, -620)
  line L3 (-240, -620) -> (-240, -630)
extrude "Channel support rail (10)" add sketch "Channel support rail sketch (10)" along normal blind 8 separate body makes body 45 in component "MM11 Rack rails and restraint stops"
ref_plane "WorkPlane12" through (0, 0, -136) normal (0, 0, 1) x (1, 0, 0) in component "MM11 Rack rails and restraint stops"
sketch "Channel support rail sketch (11)" plane through (0, 0, -136) normal (0, 0, 1) x (1, 0, 0) in component "MM11 Rack rails and restraint stops"
  line L0 (-240, -250) -> (820, -250)
  line L1 (820, -250) -> (820, -240)
  line L2 (820, -240) -> (-240, -240)
  line L3 (-240, -240) -> (-240, -250)
extrude "Channel support rail (11)" add sketch "Channel support rail sketch (11)" along normal blind 8 separate body makes body 46 in component "MM11 Rack rails and restraint stops"
ref_plane "WorkPlane13" through (0, 0, -136) normal (0, 0, 1) x (1, 0, 0) in component "MM11 Rack rails and restraint stops"
sketch "Channel support rail sketch (12)" plane through (0, 0, -136) normal (0, 0, 1) x (1, 0, 0) in component "MM11 Rack rails and restraint stops"
  line L0 (-240, -195) -> (820, -195)
  line L1 (820, -195) -> (820, -185)
  line L2 (820, -185) -> (-240, -185)
  line L3 (-240, -185) -> (-240, -195)
extrude "Channel support rail (12)" add sketch "Channel support rail sketch (12)" along normal blind 8 separate body makes body 47 in component "MM11 Rack rails and restraint stops"
ref_plane "WorkPlane14" through (0, 0, -136) normal (0, 0, 1) x (1, 0, 0) in component "MM11 Rack rails and restraint stops"
sketch "Channel support rail sketch (13)" plane through (0, 0, -136) normal (0, 0, 1) x (1, 0, 0) in component "MM11 Rack rails and restraint stops"
  line L0 (-240, 185) -> (820, 185)
  line L1 (820, 185) -> (820, 195)
  line L2 (820, 195) -> (-240, 195)
  line L3 (-240, 195) -> (-240, 185)
extrude "Channel support rail (13)" add sketch "Channel support rail sketch (13)" along normal blind 8 separate body makes body 48 in component "MM11 Rack rails and restraint stops"
ref_plane "WorkPlane15" through (0, 0, -136) normal (0, 0, 1) x (1, 0, 0) in component "MM11 Rack rails and restraint stops"
sketch "Channel support rail sketch (14)" plane through (0, 0, -136) normal (0, 0, 1) x (1, 0, 0) in component "MM11 Rack rails and restraint stops"
  line L0 (-240, 240) -> (820, 240)
  line L1 (820, 240) -> (820, 250)
  line L2 (820, 250) -> (-240, 250)
  line L3 (-240, 250) -> (-240, 240)
extrude "Channel support rail (14)" add sketch "Channel support rail sketch (14)" along normal blind 8 separate body makes body 49 in component "MM11 Rack rails and restraint stops"
ref_plane "WorkPlane16" through (0, 0, -136) normal (0, 0, 1) x (1, 0, 0) in component "MM11 Rack rails and restraint stops"
sketch "Channel support rail sketch (15)" plane through (0, 0, -136) normal (0, 0, 1) x (1, 0, 0) in component "MM11 Rack rails and restraint stops"
  line L0 (-240, 620) -> (820, 620)
  line L1 (820, 620) -> (820, 630)
  line L2 (820, 630) -> (-240, 630)
  line L3 (-240, 630) -> (-240, 620)
extrude "Channel support rail (15)" add sketch "Channel support rail sketch (15)" along normal blind 8 separate body makes body 50 in component "MM11 Rack rails and restraint stops"
ref_plane "WorkPlane17" through (0, 0, 144) normal (0, 0, 1) x (1, 0, 0) in component "MM11 Rack rails and restraint stops"
sketch "Channel support rail sketch (16)" plane through (0, 0, 144) normal (0, 0, 1) x (1, 0, 0) in component "MM11 Rack rails and restraint stops"
  line L0 (-240, -630) -> (820, -630)
  line L1 (820, -630) -> (820, -620)
  line L2 (820, -620) -> (-240, -620)
  line L3 (-240, -620) -> (-240, -630)
extrude "Channel support rail (16)" add sketch "Channel support rail sketch (16)" along normal blind 8 separate body makes body 51 in component "MM11 Rack rails and restraint stops"
ref_plane "WorkPlane18" through (0, 0, 144) normal (0, 0, 1) x (1, 0, 0) in component "MM11 Rack rails and restraint stops"
sketch "Channel support rail sketch (17)" plane through (0, 0, 144) normal (0, 0, 1) x (1, 0, 0) in component "MM11 Rack rails and restraint stops"
  line L0 (-240, -250) -> (820, -250)
  line L1 (820, -250) -> (820, -240)
  line L2 (820, -240) -> (-240, -240)
  line L3 (-240, -240) -> (-240, -250)
extrude "Channel support rail (17)" add sketch "Channel support rail sketch (17)" along normal blind 8 separate body makes body 52 in component "MM11 Rack rails and restraint stops"
ref_plane "WorkPlane19" through (0, 0, 144) normal (0, 0, 1) x (1, 0, 0) in component "MM11 Rack rails and restraint stops"
sketch "Channel support rail sketch (18)" plane through (0, 0, 144) normal (0, 0, 1) x (1, 0, 0) in component "MM11 Rack rails and restraint stops"
  line L0 (-240, -195) -> (820, -195)
  line L1 (820, -195) -> (820, -185)
  line L2 (820, -185) -> (-240, -185)
  line L3 (-240, -185) -> (-240, -195)
extrude "Channel support rail (18)" add sketch "Channel support rail sketch (18)" along normal blind 8 separate body makes body 53 in component "MM11 Rack rails and restraint stops"
ref_plane "WorkPlane20" through (0, 0, 144) normal (0, 0, 1) x (1, 0, 0) in component "MM11 Rack rails and restraint stops"
sketch "Channel support rail sketch (19)" plane through (0, 0, 144) normal (0, 0, 1) x (1, 0, 0) in component "MM11 Rack rails and restraint stops"
  line L0 (-240, 185) -> (820, 185)
  line L1 (820, 185) -> (820, 195)
  line L2 (820, 195) -> (-240, 195)
  line L3 (-240, 195) -> (-240, 185)
extrude "Channel support rail (19)" add sketch "Channel support rail sketch (19)" along normal blind 8 separate body makes body 54 in component "MM11 Rack rails and restraint stops"
ref_plane "WorkPlane21" through (0, 0, 144) normal (0, 0, 1) x (1, 0, 0) in component "MM11 Rack rails and restraint stops"
sketch "Channel support rail sketch (20)" plane through (0, 0, 144) normal (0, 0, 1) x (1, 0, 0) in component "MM11 Rack rails and restraint stops"
  line L0 (-240, 240) -> (820, 240)
  line L1 (820, 240) -> (820, 250)
  line L2 (820, 250) -> (-240, 250)
  line L3 (-240, 250) -> (-240, 240)
extrude "Channel support rail (20)" add sketch "Channel support rail sketch (20)" along normal blind 8 separate body makes body 55 in component "MM11 Rack rails and restraint stops"
ref_plane "WorkPlane22" through (0, 0, 144) normal (0, 0, 1) x (1, 0, 0) in component "MM11 Rack rails and restraint stops"
sketch "Channel support rail sketch (21)" plane through (0, 0, 144) normal (0, 0, 1) x (1, 0, 0) in component "MM11 Rack rails and restraint stops"
  line L0 (-240, 620) -> (820, 620)
  line L1 (820, 620) -> (820, 630)
  line L2 (820, 630) -> (-240, 630)
  line L3 (-240, 630) -> (-240, 620)
extrude "Channel support rail (21)" add sketch "Channel support rail sketch (21)" along normal blind 8 separate body makes body 56 in component "MM11 Rack rails and restraint stops"
ref_plane "WorkPlane23" through (0, 0, 424) normal (0, 0, 1) x (1, 0, 0) in component "MM11 Rack rails and restraint stops"
sketch "Channel support rail sketch (22)" plane through (0, 0, 424) normal (0, 0, 1) x (1, 0, 0) in component "MM11 Rack rails and restraint stops"
  line L0 (-240, -412.5) -> (820, -412.5)
  line L1 (820, -412.5) -> (820, -402.5)
  line L2 (820, -402.5) -> (-240, -402.5)
  line L3 (-240, -402.5) -> (-240, -412.5)
extrude "Channel support rail (22)" add sketch "Channel support rail sketch (22)" along normal blind 8 separate body makes body 57 in component "MM11 Rack rails and restraint stops"
ref_plane "WorkPlane24" through (0, 0, 424) normal (0, 0, 1) x (1, 0, 0) in component "MM11 Rack rails and restraint stops"
sketch "Channel support rail sketch (23)" plane through (0, 0, 424) normal (0, 0, 1) x (1, 0, 0) in component "MM11 Rack rails and restraint stops"
  line L0 (-240, -32.5) -> (820, -32.5)
  line L1 (820, -32.5) -> (820, -22.5)
  line L2 (820, -22.5) -> (-240, -22.5)
  line L3 (-240, -22.5) -> (-240, -32.5)
extrude "Channel support rail (23)" add sketch "Channel support rail sketch (23)" along normal blind 8 separate body makes body 58 in component "MM11 Rack rails and restraint stops"
ref_plane "WorkPlane25" through (0, 0, 424) normal (0, 0, 1) x (1, 0, 0) in component "MM11 Rack rails and restraint stops"
sketch "Channel support rail sketch (24)" plane through (0, 0, 424) normal (0, 0, 1) x (1, 0, 0) in component "MM11 Rack rails and restraint stops"
  line L0 (-240, 22.5) -> (820, 22.5)
  line L1 (820, 22.5) -> (820, 32.5)
  line L2 (820, 32.5) -> (-240, 32.5)
  line L3 (-240, 32.5) -> (-240, 22.5)
extrude "Channel support rail (24)" add sketch "Channel support rail sketch (24)" along normal blind 8 separate body makes body 59 in component "MM11 Rack rails and restraint stops"
ref_plane "WorkPlane26" through (0, 0, 424) normal (0, 0, 1) x (1, 0, 0) in component "MM11 Rack rails and restraint stops"
sketch "Channel support rail sketch (25)" plane through (0, 0, 424) normal (0, 0, 1) x (1, 0, 0) in component "MM11 Rack rails and restraint stops"
  line L0 (-240, 402.5) -> (820, 402.5)
  line L1 (820, 402.5) -> (820, 412.5)
  line L2 (820, 412.5) -> (-240, 412.5)
  line L3 (-240, 412.5) -> (-240, 402.5)
extrude "Channel support rail (25)" add sketch "Channel support rail sketch (25)" along normal blind 8 separate body makes body 60 in component "MM11 Rack rails and restraint stops"
ref_plane "WorkPlane27" through (-310, 0, 0) normal (1, 0, 0) x (0, 1, 0) in component "MM11 Rack rails and restraint stops"
sketch "Circular rack support frame sketch" plane through (-310, 0, 0) normal (1, 0, 0) x (0, 0, -1) in component "MM11 Rack rails and restraint stops"
  circle A0 centre (0, 0) radius 905
  circle A1 centre (0, 0) radius 895
extrude "Circular rack support frame" add sketch "Circular rack support frame sketch" along normal blind 20 separate body makes body 61 in component "MM11 Rack rails and restraint stops"
ref_plane "WorkPlane28" through (800, 0, 0) normal (1, 0, 0) x (0, 1, 0) in component "MM11 Rack rails and restraint stops"
sketch "Circular rack support frame sketch (1)" plane through (800, 0, 0) normal (1, 0, 0) x (0, 0, -1) in component "MM11 Rack rails and restraint stops"
  circle A0 centre (0, 0) radius 905
  circle A1 centre (0, 0) radius 895
extrude "Circular rack support frame (1)" add sketch "Circular rack support frame sketch (1)" along normal blind 20 separate body makes body 62 in component "MM11 Rack rails and restraint stops"
ref_plane "WorkPlane1" through (0, 0, -130) normal (0, 0, 1) x (1, 0, 0) in component "MM27 Rack conveyor channel"
sketch "Upper traction belt sketch" plane through (0, 0, -130) normal (0, 0, 1) x (1, 0, 0) in component "MM27 Rack conveyor channel"
  line L0 (-240, -15) -> (800, -15)
  line L1 (800, -15) -> (800, 15)
  line L2 (800, 15) -> (-240, 15)
  line L3 (-240, 15) -> (-240, -15)
extrude "Upper traction belt" add sketch "Upper traction belt sketch" along normal blind 2 separate body makes body 63 in component "MM27 Rack conveyor channel"
ref_plane "WorkPlane2" through (0, 0, -154) normal (0, 0, 1) x (1, 0, 0) in component "MM27 Rack conveyor channel"
sketch "Belt return sketch" plane through (0, 0, -154) normal (0, 0, 1) x (1, 0, 0) in component "MM27 Rack conveyor channel"
  line L0 (-240, -15) -> (800, -15)
  line L1 (800, -15) -> (800, 15)
  line L2 (800, 15) -> (-240, 15)
  line L3 (-240, 15) -> (-240, -15)
extrude "Belt return" add sketch "Belt return sketch" along normal blind 2 separate body makes body 64 in component "MM27 Rack conveyor channel"
ref_plane "WorkPlane3" through (0, -15, 0) normal (0, 1, 0) x (0, 0, 1) in component "MM27 Rack conveyor channel"
sketch "Drive and return pulley sketch" plane through (0, -15, 0) normal (0, 1, 0) x (1, 0, 0) in component "MM27 Rack conveyor channel"
  circle A0 centre (-240, 141) radius 12
extrude "Drive and return pulley" add sketch "Drive and return pulley sketch" along normal blind 30 separate body makes body 65 in component "MM27 Rack conveyor channel"
ref_plane "WorkPlane4" through (0, -15, 0) normal (0, 1, 0) x (0, 0, 1) in component "MM27 Rack conveyor channel"
sketch "Drive and return pulley sketch (1)" plane through (0, -15, 0) normal (0, 1, 0) x (1, 0, 0) in component "MM27 Rack conveyor channel"
  circle A0 centre (800, 141) radius 12
extrude "Drive and return pulley (1)" add sketch "Drive and return pulley sketch (1)" along normal blind 30 separate body makes body 66 in component "MM27 Rack conveyor channel"
ref_plane "WorkPlane1" through (0, 0, -180) normal (0, 0, 1) x (1, 0, 0) in component "MM28 Sliding receiver conveyor"
sketch "Receiver conveyor side beam sketch" plane through (0, 0, -180) normal (0, 0, 1) x (1, 0, 0) in component "MM28 Sliding receiver conveyor"
  line L0 (-2100, -186) -> (-930, -186)
  line L1 (-930, -186) -> (-930, -164)
  line L2 (-930, -164) -> (-2100, -164)
  line L3 (-2100, -164) -> (-2100, -186)
extrude "Receiver conveyor side beam" add sketch "Receiver conveyor side beam sketch" along normal blind 32 separate body makes body 67 in component "MM28 Sliding receiver conveyor"
ref_plane "WorkPlane2" through (0, 0, -180) normal (0, 0, 1) x (1, 0, 0) in component "MM28 Sliding receiver conveyor"